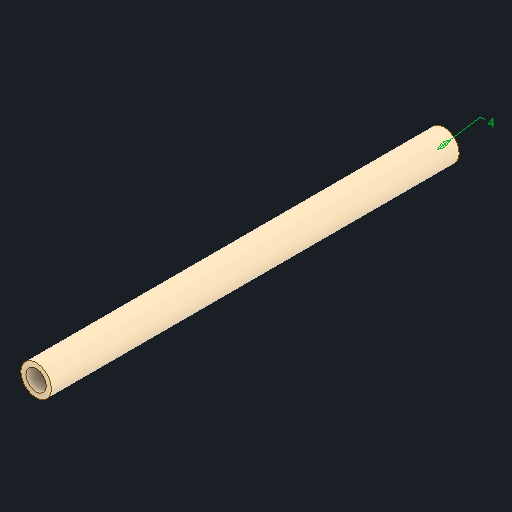
# Autodesk Inventor part: tupe-12
Saved by Autodesk Inventor 2026.2 (Build 302298010, 298A)
## iProperties
Created: 2026-09-23
Part Number: tupe-12
Material: PE tube Festo PEN-6x1 (LDPE, Xiao 2007, D12-3)
Document SubType Name: Modeling
Designer: user
Density: 0.942 g/cm^3
Appearance: Smooth - Off-White
Description: Copy of tupe-12, geometry unchanged; PE tube material (LDPE closest, density from Festo PEN).
Mass: 1.18375 g
Surface Area: 25.4469 cm^2
Volume: 1.25664 cm^3
Author: user
Autodesk Inventor part; units mm, degrees
ref_plane "YZ Plane" through (0, 0, 0) normal (1, 0, 0) x (0, 1, 0)
ref_plane "XZ Plane" through (0, 0, 0) normal (0, 1, 0) x (-1, 0, 0)
ref_plane "XY Plane" through (0, 0, 0) normal (0, 0, 1) x (1, 0, 0)
sketch "Sketch1" plane through (0, 0, 0) normal (0, 0, 1) x (1, 0, 0)
  circle A0 centre (-0.3096, 0) radius 2
  point P0 (0, 0)
  dimension "d0" = 4
  constraints: 1 centre point
  measures "d0" diameter of A0
extrude "Extrusion1" add sketch "Sketch1" along normal blind 80
shell "Shell1" thickness 1 outward yes removed faces 2 at (0.0333, 0.4805, 0) at (0.0333, 0.4805, 80)
body "Solid1"
